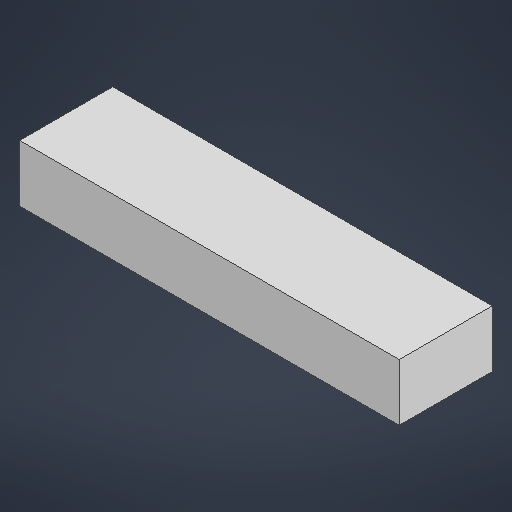
# Autodesk Inventor part: 2_09_plaque_Cmanagement
Saved by Autodesk Inventor 2026 (Build 300175000, 175)
## iProperties
Created: 2025-06-09
Part Number: 2_09_plaque_Cmanagement
Material: Générique
Document SubType Name: Modeling
Designer: Diogo
Density: 1 g/cm^3
Appearance: Par défaut
Author: Diogo
Autodesk Inventor part; units mm, degrees
ref_plane "YZ Plane" through (0, 0, 0) normal (1, 0, 0) x (0, 1, 0)
ref_plane "XZ Plane" through (0, 0, 0) normal (0, 1, 0) x (-1, 0, 0)
ref_plane "XY Plane" through (0, 0, 0) normal (0, 0, 1) x (1, 0, 0)
sketch "Esquisse1" plane through (0, 0, 0) normal (0, 1, 0) x (-1, 0, 0)
  line L0 (0, 0) -> (20, 0)
  line L1 (20, 0) -> (20, -4.9)
  line L2 (20, -4.9) -> (0, -4.9)
  line L3 (0, -4.9) -> (0, 0)
  dimension "d0" = 20
  dimension "d1" = 4.9
  constraints: 8 end point, 2 parallel, 1 horizontal, 1 perpendicular
  measures "d0" distance of L1.end L2.end
  measures "d1" distance of L0.end L1.end
extrude "Extrusion1" add sketch "Esquisse1" along normal blind 3
